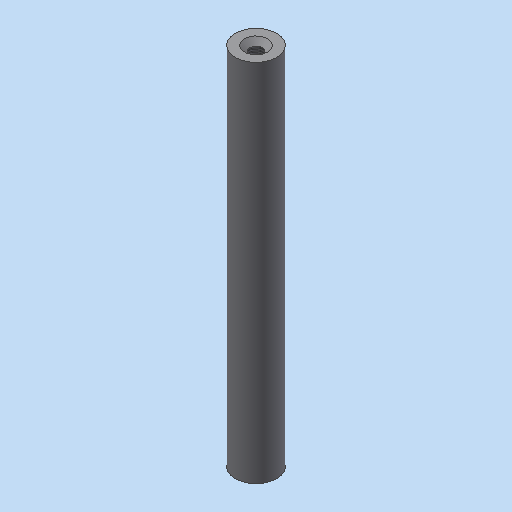
# Autodesk Inventor part: MM0948AN100_G01_190
Saved by Autodesk Inventor 2023.3 (Build 273359000, 359)
## iProperties
Created: 2023-03-23
Part Number: MM0948AN100_G01_190
Material: 1.2842 90MnCrV8
Document SubType Name: Modeling
Designer: wed1an
Density: 7.85 g/cm^3
Appearance: silber AnP
Mass: 26.929 g
Surface Area: 19.7856 cm^2
Volume: 3.43044 cm^3
Description: =<RBPARTNOTITLE2>
RBMATERIAL: =<Material>
RBMATNO: =<Part Number>
RBPARTMADEOF: Rd. 8 x 77 (FM)
RBPARTNO: SIEHE MNR
RBPARTNOTITLE1: manufactured part
RBPARTNOTITLE2: Anfertigungsteil
MaxAbmaße: 77 x 8 x 8 (FM)
AnP_Material_aktuell: =<Material>
AnP_Kommentar_aktuell: =<Comments>
RBSURFACE: chemically nickel-coated
AnP_Kategorie: 1
AnP_Material: =<Material>
RBDRAWINGMISSINGSPEC: --
RBSURFACE2: chem. vernickelt
Author: FH/Wi
Keywords: =<RBPARTMADEOF>
Comments: =<RBSURFACE2>
Revision Number: 01
Autodesk Inventor part; units mm, degrees
ref_plane "YZ Plane" through (0, 0, 0) normal (1, 0, 0) x (0, 1, 0)
ref_plane "XZ Plane" through (0, 0, 0) normal (0, 1, 0) x (-1, 0, 0)
ref_plane "XY Plane" through (0, 0, 0) normal (0, 0, 1) x (1, 0, 0)
sketch "Skizze1" plane through (0, 0, 0) normal (0, 0, 1) x (1, 0, 0)
  circle A0 centre (0, 0) radius 4
  dimension "d0" = 8
  constraints: 1 centre point, 1 coincident
  measures "d0" diameter of A0
extrude "Extrusion1" add sketch "Skizze1" along normal blind 70
sketch "Skizze2" plane through (0, 0, 70) normal (0, 0, 1) x (1, 0, 0)
  circle A0 centre (0, 0) radius 4 projected
  constraints: 1 coincident
hole "Bohrung1" at (0, 0, 70) direction (0, 0, -1) diameter 2.459 depth 8 tip angle 118 thread size "M3x0.5" designation "M3" class "6H" standard "ISO Metric profile"
sketch "Skizze3" plane through (0, 0, 0) normal (0, 0, -1) x (-1, 0, 0)
  circle A0 centre (0, 0) radius 4 projected
  constraints: 1 coincident
hole "Bohrung2" at (0, 0, 0) direction (0, 0, 1) diameter 2.459 depth 8 tip angle 118 thread size "M3x0.5" designation "M3" class "6H" standard "ISO Metric profile"
chamfer "Fase2" distance 1 angle 45 2 edges at (0, 1.2295, 70) (0, -1.2295, 0)
